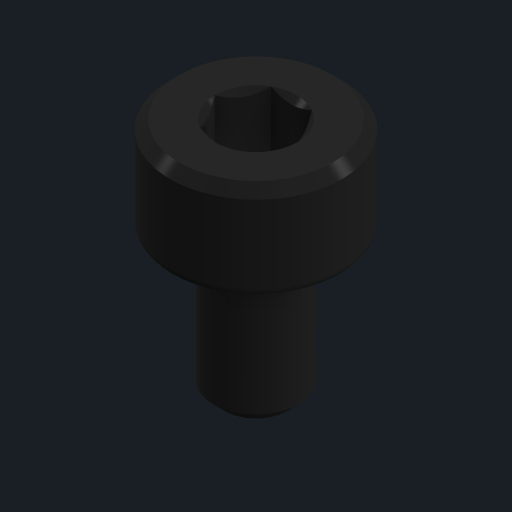
# Autodesk Inventor part: Parafuso Allen Cabeça Cilíndrica DIN 912 - M4 - 12.9
Saved by Autodesk Inventor 2026.1 (Build 301233000, 233)
## iProperties
Created: 2025-07-13
Part Number: Parafuso Allen Cabeça Cilíndrica DIN 912 - M4 - 12.9
Material: Genérico
Document SubType Name: Modeling
Designer: Cliente
Mass: 0.200613 g
Surface Area: 2.50209 cm^2
Volume: 0.200613 cm^3
Density: 1 g/cm^3
Appearance: Aço - Polido(1)
Mass: 2.48365 g
Surface Area: 5.69644 cm^2
Volume: 0.316389 cm^3
Density: 7.85 g/cm^3
Author: Cliente
Autodesk Inventor part; units mm, degrees
ref_plane "YZ Plane" through (0, 0, 0) normal (1, 0, 0) x (0, 1, 0)
ref_plane "XZ Plane" through (0, 0, 0) normal (0, 1, 0) x (-1, 0, 0)
sketch "Esboço1" plane through (0, 0, 0) normal (0, 0, 1) x (1, 0, 0)
  line L0 (0, 0) -> (0, 4)
  line L1 (0, 4) -> (3.21, 4)
  line L2 (3.61, 3.6) -> (3.61, 0)
  line L3 (0, 0) -> (0, -6)
  line L4 (0, 0) -> (2.35, 0)
  line L5 (2.35, 0) -> (3.61, 0)
  arc A0 (2.35, 0) -> (1.8661, -0.3742) centre (2.35, -0.5) ccw
  line L6 (1.8661, -0.3742) -> (1.8285, -0.5189)
  arc A1 (1.8285, -0.5189) -> (1.791, -0.812) centre (2.956, -0.812) ccw
  line L7 (1.791, -0.812) -> (1.791, -5.51)
  line L8 (0, -6) -> (1.301, -6)
  line L9 (1.301, -6) -> (1.791, -5.51)
  line L10 (3.21, 4) -> (3.61, 3.6)
  line L11 (0, 0) -> (3.265, 0)
  arc A2 (3.265, 0) -> (3.61, 0.345) centre (3.265, 0.345) ccw
  line L12 (3.265, 0) -> (3.61, 0.345) construction
  line L13 (3.265, 0) -> (3.7529, 0) construction
  line L14 (1.791, -0.812) -> (0, -0.812)
  line L15 (3.61, 0) -> (3.61, 0.5)
  line L16 (3.61, 0.5) -> (0, 0.5)
  line L17 (1.791, -10.54) -> (1.361, -10.54)
  line L18 (1.361, -10.54) -> (0, -10.54)
  arc A3 (1.391, -10.4863) -> (1.361, -10.54) centre (1.424, -10.54) ccw
  arc A4 (1.7586, -10.2607) -> (1.791, -10.2028) centre (1.723, -10.2028) ccw
  line L19 (1.391, -10.4863) -> (1.7586, -10.2607)
  line L20 (0, -13.448) -> (0, 6.908) projected
  point P0 (3.61, 4)
  point P1 (1.791, -6)
  point P2 (1.546, -5.755)
  dimension "d0" = 4
  dimension "d1" = 3.61
  dimension "d2" = 6
  dimension "d3" = 2.35
  dimension "d4" = 0.5
  dimension "d5" = 1.165
  dimension "d7" = 0.812
  dimension "d8" = 3.582
  dimension "d9" = 0.49
  dimension "d10" = 0.49
  dimension "d11" = 0.4
  dimension "d12" = 0.4
  dimension "d13" = 3.265
  dimension "d14" = 45
  dimension "d59" = 0.5
  dimension "d62" = 0.43
  dimension "d63" = 10.54
  dimension "d64" = 0.068
  dimension "d65" = 0.063
  dimension "d66" = 31.54
  constraints: 40 end point, 13 point on line, 10 point on circle, 8 tangent, 5 centre point, 4 horizontal, 4 perpendicular, 3 vertical, 2 horizontal alignment, 1 collinear, 1 equal length, 1 line through centre, 1 midpoint
  measures "d0" distance of L0.start L0.end
  measures "d1" distance of L0.end point (3.61, 4)
  measures "d2" distance of L0.start L3.end
  measures "d3" distance of L0.start L4.end
  measures "d4" radius of A0
  measures "d5" radius of A1
  measures "d7" distance from line of L5 L7.start
  measures "d8" diameter of L7 L3
  measures "d9" distance of L8.end point (1.791, -6)
  measures "d10" distance of L7.end point (1.791, -6)
  measures "d11" distance of L1.end point (3.61, 4)
  measures "d12" distance of L2.start point (3.61, 4)
  measures "d13" distance of L0.start L11.end
  measures "d14" angle of L13 L12
  measures "d59" distance of L2.end L15.end
  measures "d62" distance of L17.start L17.end
  measures "d63" distance of L18.end L0.start
  measures "d64" radius of A4
  measures "d65" radius of A3
  measures "d66" angle of L17 L19
revolve "Revolução1" add sketch "Esboço1" angle 360 about axis through (0, 0, 0) along (0, 1, 0) contours L0 L16 L2 A2 L5 L4 | L0 L1 L10 L2 L16 | L14 L7 L9 L8 L3
sketch "Esboço2" plane through (0, 4, 0) normal (0, 1, 0) x (1, 0, 0)
  circle A0 centre (0, 0) radius 1.301 projected
  line L0 (1.7234, 0) -> (0.8617, -1.4925)
  line L1 (0.8617, -1.4925) -> (-0.8617, -1.4925)
  line L2 (-0.8617, -1.4925) -> (-1.7234, 0)
  line L3 (-1.7234, 0) -> (-0.8617, 1.4925)
  line L4 (-0.8617, 1.4925) -> (0.8617, 1.4925)
  line L5 (0.8617, 1.4925) -> (1.7234, 0)
  dimension "d18" = 2.985
  constraints: 12 end point, 1 coincident, 1 horizontal, 13 other
  measures "d18" distance between parallel lines of L1 L4
extrude "Extrusão1" cut sketch "Esboço2" against normal blind 2.353 contours A0 | L0 L1 L2 L3 L4 L5
sketch "Esboço3" plane through (0, 0, 0) normal (0, 0, 1) x (1, 0, 0)
  line L0 (-1.7234, 4) -> (-0.8617, 4) projected
  line L1 (-1.7234, 4) -> (-1.7234, 1.647) projected
  line L2 (-1.7234, 1.647) -> (-0.8617, 1.647) projected
  line L3 (-0.8617, 4) -> (-0.8617, 1.647) projected
  line L4 (0.8617, 4) -> (1.7234, 4) projected
  line L5 (0.8617, 4) -> (0.8617, 1.647) projected
  line L6 (0.8617, 1.647) -> (1.7234, 1.647) projected
  line L7 (1.7234, 4) -> (1.7234, 1.647) projected
  line L8 (-1.7234, 1.647) -> (-0.7781, 0.8954)
  arc A0 (-1.7234, 1.647) -> (1.7234, 1.647) centre (0, 3.8144) ccw
  line L9 (0, 1.647) -> (0, 1.0453)
  line L10 (-0.8617, 1.647) -> (0.8617, 1.647) projected
  line L11 (-1.7234, 4) -> (-0.8617, 3.1383)
  line L12 (-0.8617, 4) -> (-0.8617, 1.647) projected
  line L13 (-1.7234, 4) -> (-0.5048, 4) construction
  point P0 (0, 0)
  dimension "d21" = 128.49
  dimension "d25" = 45
  constraints: 8 end point, 3 point on circle, 1 centre point, 1 equal length, 1 horizontal, 1 line through centre, 1 point on line, 1 tangent
  measures "d21" angle of L8 L1
  measures "d25" angle of L11 L13
revolve "Revolução2" cut sketch "Esboço3" angle 360 about axis through (0, 1.647, 0) along (0, -1, 0) contours L0 L3 L11 | L2 L10 L9 A0
ref_plane "Plano de trabalho1" through (0, 3, 0) normal (0, 1, 0) x (1, 0, 0)
sketch "Esboço4" plane through (0, 3, 0) normal (0, 1, 0) x (1, 0, 0)
  circle A0 centre (0, 0) radius 3.61 projected
  line L0 (-1.7234, 0) -> (-0.8617, 1.4925) projected
  line L1 (-0.8617, 1.4925) -> (0.8617, 1.4925) projected
  line L2 (-0.8617, -1.4925) -> (-1.7234, 0) projected
  line L3 (0.8617, -1.4925) -> (-0.8617, -1.4925) projected
  line L4 (1.7234, 0) -> (0.8617, -1.4925) projected
  line L5 (0.8617, 1.4925) -> (1.7234, 0) projected
extrude "Extrusão2" add sketch "Esboço4" against normal blind 2
sketch "Esboço5" plane through (0, 0, 0) normal (0, 0, 1) x (1, 0, 0)
  line L0 (-1.791, -5.51) -> (-1.791, -0.812) projected
  line L1 (1.791, -5.51) -> (-1.791, -5.51) projected
  line L2 (-1.7725, -9.51) -> (1.7725, -9.51)
  line L3 (-1.7725, -9.51) -> (-1.7725, -8.4332)
  line L4 (-1.621, -9.51) -> (1.621, -9.51)
  line L5 (-1.621, -9.51) -> (-1.621, -8.4332)
  line L6 (-2.0756, -9.51) -> (-2.0756, -8.4332)
  line L7 (-1.4694, -9.51) -> (-1.4694, -8.4332)
  line L8 (-2.0756, -9.51) -> (-1.4694, -9.16)
  line L9 (-2.0756, -9.51) -> (-1.3756, -9.51) construction
  line L10 (-1.4694, -9.16) -> (-2.0756, -8.81)
  arc A0 (-1.621, -9.2475) -> (-1.621, -9.0725) centre (-1.6715, -9.16) ccw
  line L11 (-1.2821, -10.4783) -> (1.1369, -10.4783)
  line L12 (-1.6001, -10.5808) -> (1.9449, -10.5808)
  line L13 (-1.6001, -5.51) -> (-1.6001, -4.5566)
  line L14 (-1.4694, -5.51) -> (-1.4694, -4.5566)
  line L15 (-1.9628, -9.51) -> (-1.9628, -8.5566)
  point P0 (0, 0)
  point P1 (0, -9.51)
  point P2 (-1.5705, -9.16)
  dimension "d32" = 3.545
  dimension "d33" = 2.419
  dimension "d39" = 0.317
  dimension "d40" = 0.342
  dimension "d41" = 30
  dimension "d42" = 60
  dimension "d61" = 0.2205
  dimension "d72" = 2.419
  dimension "d73" = 3.545
  constraints: 28 end point, 7 point on line, 6 vertical, 5 horizontal, 3 horizontal alignment, 3 point on circle, 2 midpoint, 1 centre point, 1 equal length, 1 perpendicular, 1 tangent, 5 other
  measures "d32" distance of L2.start L2.end
  measures "d41" angle of L9 L8
  measures "d42" angle of L8 L10
  measures "d61" distance from line of L0 point (-1.57, -9.16)
  measures "d72" distance of L11.start L11.end
  measures "d73" distance of L12.start L12.end
feature "Espiral1" [suppressed]
feature "Espiral2" [suppressed]
revolve "Revolução3" add sketch "Esboço1" angle 360 about axis through (0, 0, 0) along (0, -1, 0) contours L4 A0 L6 A1 L14 L3 | L0 L16 L2 A2 L5 L4
revolve "Revolução4" [suppressed]
revolve "Revolução5" [suppressed]
equation "\"d10\" = d9"
equation "\"d12\" = d11"
